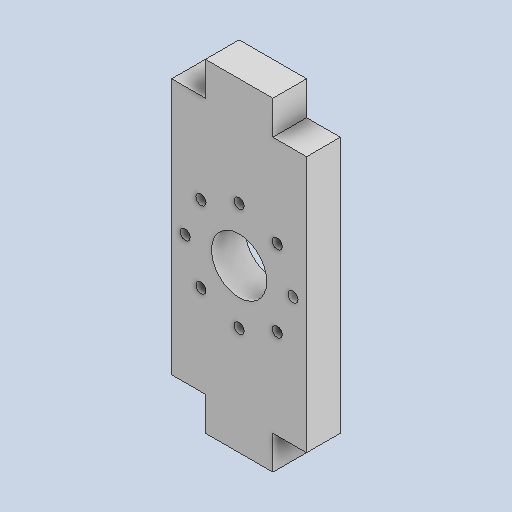
# Autodesk Inventor part: ShoulderFrontL
Saved by Autodesk Inventor 2025.2 (Build 292293000, 293)
## iProperties
Created: 2025-06-27
Part Number: ShoulderFrontL
Material: Generic
Document SubType Name: Modeling
Designer: ricoa
Density: 1 g/cm^3
Appearance: Default
Author: ricoa
Autodesk Inventor part; units mm, degrees
ref_plane "YZ Plane" through (0, 0, 0) normal (1, 0, 0) x (0, 1, 0)
ref_plane "XZ Plane" through (0, 0, 0) normal (0, 1, 0) x (-1, 0, 0)
ref_plane "XY Plane" through (0, 0, 0) normal (0, 0, 1) x (1, 0, 0)
sketch "Sketch1" plane through (0, 0, 0) normal (0, 0, 1) x (1, 0, 0)
  line L0 (0, -43) -> (10, -43) projected
  line L1 (-5, -38) -> (0, -38) projected
  line L2 (0, -43) -> (0, -38) projected
  line L3 (10, -43) -> (10, -38) projected
  line L4 (10, -38) -> (15, -38) projected
  line L5 (0, 5) -> (10, 5) projected
  line L6 (-5, 0) -> (0, 0) projected
  line L7 (0, 0) -> (0, 5) projected
  line L8 (10, 0) -> (10, 5) projected
  line L9 (10, 0) -> (15, 0) projected
  line L10 (-5, -38) -> (-5, 0)
  line L11 (15, -38) -> (15, 0)
  circle A0 centre (5, -19) radius 4.1
  dimension "d0" = 8.2
  constraints: 4 end point, 1 centre point, 1 parallel, 1 vertical
  measures "d0" diameter of A0
extrude "Extrusion1" add sketch "Sketch1" along normal blind 5
sketch "Sketch2" plane through (0, 0, 0) normal (0, 0, -1) x (-1, 0, 0)
  circle A0 centre (-5, -19) radius 9.75 projected
  circle A1 centre (-5, -19) radius 4.75 projected
  circle A2 centre (3, -19) radius 0.75 projected
  circle A3 centre (0.6569, -24.6569) radius 0.75 projected
  circle A4 centre (-5, -27) radius 0.75 projected
  circle A5 centre (-10.6569, -24.6569) radius 0.75 projected
  circle A6 centre (-13, -19) radius 0.75 projected
  circle A7 centre (-10.6569, -13.3431) radius 0.75 projected
  circle A8 centre (-5, -11) radius 0.75 projected
  circle A9 centre (0.6569, -13.3431) radius 0.75 projected
  point P0 (0, 0)
extrude "Extrusion2" cut sketch "Sketch2" against normal blind 5 contours A2 | A3 | A4 | A5 | A6 | A7 | A8 | A9
body "Solid1"
